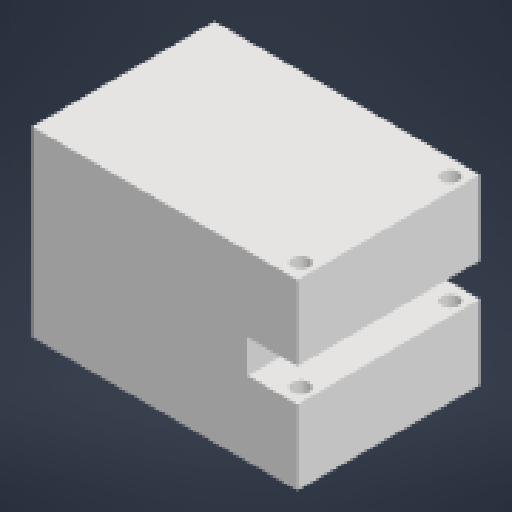
# Autodesk Inventor part: soportePinza
Saved by Autodesk Inventor 2027.1 (Build 311270010, 270A)
## iProperties
Created: 2026-11-02
Part Number: soportePinza
Material: Genérico
Document SubType Name: Modeling
Designer: MANGEL
Density: 1 g/cm^3
Appearance: Valor por defecto
Author: MANGEL
Autodesk Inventor part; units mm, degrees
ref_plane "YZ Plane" through (0, 0, 0) normal (1, 0, 0) x (0, 1, 0)
ref_plane "XZ Plane" through (0, 0, 0) normal (0, 1, 0) x (-1, 0, 0)
ref_plane "XY Plane" through (0, 0, 0) normal (0, 0, 1) x (1, 0, 0)
sketch "Boceto1" plane through (0, 0, 0) normal (0, 1, 0) x (-1, 0, 0)
  line L0 (40, 27.5) -> (-40, 27.5)
  line L1 (-40, 27.5) -> (-40, -27.5)
  line L2 (-40, -27.5) -> (40, -27.5)
  line L3 (40, -27.5) -> (40, 27.5)
  line L4 (40, 27.5) -> (-40, -27.5) construction
  line L5 (-40, 27.5) -> (40, -27.5) construction
  point P0 (0, 0)
  dimension "d0" = 80
  dimension "d1" = 55
  constraints: 12 end point, 2 midpoint, 2 parallel, 1 horizontal, 1 perpendicular
  measures "d0" distance of L1.end L2.end
  measures "d1" distance of L0.end L1.end
extrude "Extrusión1" add sketch "Boceto1" along normal blind 55
sketch "Boceto2" plane through (-40, 0, 27.5) normal (0, 0, 1) x (1, 0, 0)
  line L0 (80, 32.5) -> (60, 32.5)
  line L1 (60, 32.5) -> (60, 22.5)
  line L2 (60, 22.5) -> (80, 22.5)
  line L3 (80, 22.5) -> (80, 32.5)
  line L4 (80, 0) -> (80, 55) projected
  point P0 (40, 0)
  point P1 (60, 27.5)
  point P2 (80, 27.5)
  dimension "d4" = 20
  dimension "d5" = 10
  constraints: 8 end point, 2 midpoint, 2 parallel, 1 collinear, 1 horizontal, 1 horizontal alignment, 1 perpendicular
  measures "d4" distance of L0.start L0.end
  measures "d5" distance of L0.end L1.end
extrude "Extrusión2" cut sketch "Boceto2" against normal through all
sketch "Boceto3" plane through (0, 55, 0) normal (0, 1, 0) x (1, 0, 0)
  circle A0 centre (32, -17.5) radius 2.5
  line L0 (0, 0) -> (40, 0) construction
  line L1 (40, -27.5) -> (40, 27.5) construction
  line L2 (-40, -27.5) -> (40, -27.5) construction
  circle A1 centre (32, 17.5) radius 2.5
  dimension "d8" = 5
  dimension "d9" = 10
  dimension "d10" = 8
  constraints: 2 centre point, 2 end point, 1 midpoint, 1 symmetric about line, 1 other
  measures "d8" diameter of A0
  measures "d9" distance from line of L2 A0.centre
  measures "d10" distance from line of L1 A0.centre
extrude "Extrusión3" cut sketch "Boceto3" against normal through all
